testMale (Autodesk Fusion 360 design; units mm, degrees)
Autodesk Fusion 360 part; units mm, degrees
sketch "Sketch1" plane through (0, 0, 0) normal (0, 1, 0) x (1, 0, 0)
  line L0 (20, -20) -> (-20, -20)
  line L1 (-20, -20) -> (-20, 20)
  line L2 (-20, 20) -> (20, 20)
  line L3 (20, 20) -> (20, -20)
  line L4 (20, -20) -> (-20, 20) construction
  line L5 (-20, -20) -> (20, 20) construction
  constraint perpendicular L0 L1
  constraint parallel L0 L2
  constraint parallel L1 L3
  constraint horizontal L0
  constraint coincident L4 origin
  constraint coincident L5 origin
extrude "Extrude1" add sketch "Sketch1" along normal blind 5
sketch "Sketch2" plane through (0, 5, 0) normal (0, 1, 0) x (-1, 0, 0)
  line L0 (-20, -20) -> (20, -20)
  line L1 (20, -20) -> (20, 20)
  line L2 (20, 20) -> (-20, 20)
  line L3 (-20, 20) -> (-20, -20)
  circle A0 centre (0, 0) radius 5
  dimension "d3" = 10
  constraint coincident A0.centre origin
  measures "d3" diameter of A0
extrude "Extrude2" add sketch "Sketch2" along normal blind 5 contours A0
sketch "Sketch3" plane through (0, 10, 0) normal (0, 1, 0) x (-1, 0, 0)
  circle A0 centre (0, 0) radius 5
  circle A1 centre (0, 0) radius 5
  line L0 (0, 0) -> (-13.563, 0) construction
  line L1 (0, 0) -> (10, 0) construction
  line L2 (0, 0) -> (0, -9) construction
  line L3 (0, 0) -> (0, 9.6146) construction
  line L4 (5, 0) -> (6.7365, -9.8481)
  line L5 (5, 0) -> (15, 0) construction
  line L6 (-5, 0) -> (-6.7365, -9.8481)
  line L7 (-5, 0) -> (5, 0) construction
  line L8 (6.7365, -9.8481) -> (-6.7365, -9.8481)
  line L9 (5, 0) -> (6.7365, 9.8481)
  line L10 (5, 0) -> (15, 0) construction
  line L11 (-5, 0) -> (-6.7365, 9.8481)
  line L12 (-5, 0) -> (5, 0) construction
  line L13 (-6.7365, 9.8481) -> (6.7365, 9.8481)
  point P0 (-5, 0)
  dimension "d6" = 80
  dimension "d7" = 10
  dimension "d8" = 100
  dimension "d9" = 10
  dimension "d10" = 80
  dimension "d11" = 10
  dimension "d12" = 100
  dimension "d13" = 10
  constraint coincident A0.centre A1.centre
  constraint horizontal L0
  constraint parallel L0 L1
  constraint perpendicular L1 L2
  constraint perpendicular L1 L3
  constraint midpoint L1 L4.start
  constraint horizontal L5
  constraint coincident P0 L6.start
  constraint horizontal L7
  constraint horizontal L10
  constraint horizontal L12
  constraint horizontal L13
  measures "d6" angle of L4 L5
  measures "d7" distance of L4.start L4.end
  measures "d8" angle of L6 L7
  measures "d9" distance of P0 L6.end
  measures "d10" angle of L9 L10
  measures "d11" distance of L4.start L9.end
  measures "d12" angle of L11 L12
  measures "d13" distance of P0 L11.end
extrude "Extrude3" add sketch "Sketch3" along normal blind 5
chamfer "Chamfer1" distance 0.75 angle 45 14 edges at (-5.8682, 10, 4.924) (-5.8682, 15, 4.924) (-6.7365, 12.5, 9.8481) (0, 15, 9.8481) (0, 10, 9.8481) (5.8682, 10, 4.924) (5.8682, 15, 4.924) (5.8682, 15, -4.924) (5.8682, 10, -4.924) (0, 15, -9.8481) (0, 10, -9.8481) (-6.7365, 12.5, -9.8481) (-5.8682, 15, -4.924) (-5.8682, 10, -4.924)
fillet "Fillet1" radius 10 2 edges at (-5, 12.5, 0) (5, 12.5, 0)
fillet "Fillet2" radius 9.5 4 edges at (20, 2.5, 20) (20, 2.5, -20) (-20, 2.5, -20) (-20, 2.5, 20)
component "Component" placed x (1, 0, 0) y (0, 1, 0) z (0, 0, 1) at (0, 0, 0)
